Untitled (Autodesk Fusion 360 design; units mm, degrees)
Autodesk Fusion 360 part; units mm, degrees
note: some values were not read from the file. Set by a fixed rule: which face or edge a step refers to.
other "Base Mesh Feature1"
sketch "Sketch1" plane through (0, 0, 0) normal (0, 1, 0) x (1, 0, 0)
sketch "Sketch2" plane through (0, 0, 0) normal (0, 0, 1) x (1, 0, 0)
  line L0 (1, 1) -> (38, 1)
  line L1 (38, 1) -> (38, -19)
  line L2 (38, -19) -> (1, -19)
  line L3 (1, -19) -> (1, 1)
  line L4 (38, -9.5531) -> (28, -9.5531)
  line L5 (28, -9.5531) -> (28, -8.4531)
  line L6 (28, -8.4531) -> (38, -8.4531)
  line L7 (38, -8.4531) -> (38, -9.5531)
  line L8 (1, -9.5536) -> (11, -9.5536)
  line L9 (11, -9.5536) -> (11, -8.4536)
  line L10 (11, -8.4536) -> (1, -8.4536)
  line L11 (1, -8.4536) -> (1, -9.5536)
  dimension "d1" = 10
  dimension "d2" = 1.1
  dimension "d3" = 10
  dimension "d4" = 1.1
  constraint horizontal L0
  constraint vertical L1
  constraint horizontal L2
  constraint vertical L3
  constraint horizontal L4
  constraint vertical L5
  constraint horizontal L6
  constraint vertical L7
  constraint coincident L1 L4.start
  constraint horizontal L8
  constraint vertical L9
  constraint horizontal L10
  constraint vertical L11
  constraint coincident L3 L8.start
  measures "d1" distance of L4.start L4.end
  measures "d2" distance of L4.start L6.end
  measures "d3" distance of L8.start L8.end
  measures "d4" distance of L8.start L10.end
sketch "Sketch3" plane through (0, 0, 0) normal (1, 0, 0) x (0, 0, -1)
extrude "Extrude1" add sketch "Sketch2" along normal blind 29 makes body 1
extrude "Extrude2" cut sketch "Sketch2" along normal blind 22 contours L3 L8 L9 L10 L11 | L1 L4 L5 L6 L7 bodies 1
sketch "Sketch4" plane through (0, -19, 0) normal (0, -1, 0) x (1, 0, 0)
  line L0 (1, 0) -> (38, 0)
  line L1 (38, 0) -> (38, 29)
  line L2 (38, 29) -> (1, 29)
  line L3 (1, 29) -> (1, 0)
  line L4 (38, 0) -> (65.5, 0)
  line L5 (65.5, 0) -> (65.5, 29)
  line L6 (65.5, 29) -> (38, 29)
  line L7 (38, 29) -> (38, 0)
  dimension "d11" = 27.5
  dimension "d12" = 29
  constraint horizontal L4
  constraint vertical L5
  constraint horizontal L6
  constraint vertical L7
  constraint coincident L0.end L1.start
  measures "d11" distance of L0.end L4.end
  measures "d12" distance of L0.end L1.end
extrude "Extrude3" add sketch "Sketch4" against normal blind 9 separate body contours L1 L4 L5 L6 L7 makes body 2
sketch "Sketch5" plane through (0, -19, 0) normal (0, -1, 0) x (1, 0, 0)
  line L0 (38, 29) -> (38, 0)
  line L1 (38, 0) -> (65.5, 0)
  line L2 (65.5, 0) -> (65.5, 29)
  line L3 (65.5, 29) -> (38, 29)
  line L4 (65.5, 29) -> (78.5, 29)
  line L5 (78.5, 29) -> (78.5, 0)
  line L6 (78.5, 0) -> (65.5, 0)
  line L7 (65.5, 0) -> (65.5, 29)
  constraint horizontal L4
  constraint vertical L5
  constraint horizontal L6
  constraint vertical L7
  constraint coincident L2.end L3.start
extrude "Extrude4" add sketch "Sketch5" along normal blind 27.5 and the other way blind 9 contours L2 L4 L5 L6 L7 bodies 2
copy_body "CopyPasteBodies1" bodies 1 makes body 3
move_body "Move1" bodies 3 to x (0, -1, 0) y (1, 0, 0) z (0, 0, 1) at (84.4226, -51.1247, 0)
move_body "Move2" bodies 3 to x (1, 0, 0) y (0, 1, 0) z (0, 0, 1) at (0.0774, 5.6247, 0)
sketch "Sketch6" plane through (0, -19, 0) normal (0, -1, 0) x (1, 0, 0)
  line L0 (1, 0) -> (38, 0)
  line L1 (38, 0) -> (38, 29)
  line L2 (38, 29) -> (1, 29)
  line L3 (1, 29) -> (1, 0)
  line L4 (1, 29) -> (38, 29)
  line L5 (38, 29) -> (38, 0)
  line L6 (38, 0) -> (1, 0)
  line L7 (1, 0) -> (1, 29)
  constraint horizontal L4
  constraint vertical L5
  constraint horizontal L6
  constraint vertical L7
  constraint coincident L0.end L1.start
  constraint coincident L2.end L3.start
extrude "Extrude5" add sketch "Sketch6" along normal blind 64.5 bodies 1
extrude "Extrude6" add 1 faces at (65.5, -71.1667, 9.6667) along direction (-1, 0, 0) blind 64.5 on bodies 3 bodies 3 1
chamfer "Chamfer1" distance 15 angle 45 1 edges at (1, -83.5, 14.5) tangent chain off on bodies 3
chamfer "Chamfer2" distance 15 angle 45 1 edges at (38, -46.5, 14.5) tangent chain off on bodies 3
extrude "Extrude7" cut 1 faces at (76.0464, -53.1667, 7.3333) along direction (1, 0, 0) blind 0.001 on bodies 3 bodies 3
extrude "Extrude8" add 1 faces at (76.0474, -53.1667, 7.3333) along direction (-1, 0, 0) blind 0.7 on bodies 3 bodies 3
extrude "Extrude9" add 1 faces at (76.0469, -76.8333, 7.3333) along direction (-1, 0, 0) blind 0.7 on bodies 3 bodies 3
extrude "Extrude10" add 1 faces at (31.3333, -8.4531, 7.3333) along direction (0, -1, 0) blind 0.7 on bodies 3 bodies 3
sketch "Sketch7" plane through (0, -8.4536, 0) normal (0, -1, 0) x (1, 0, 0)
  line L0 (1, 0) -> (11, 0)
  line L1 (11, 0) -> (11, 22)
  line L2 (11, 22) -> (1, 22)
  line L3 (1, 22) -> (1, 0)
extrude "Extrude11" add sketch "Sketch7" along normal blind 0.7 bodies 3
extrude "Extrude12" cut 1 faces at (34.6667, -9.5531, 7.3333) along direction (0, -1, 0) blind 0.25 on bodies 3 bodies 3
extrude "Extrude13" cut 1 faces at (4.3333, -9.5536, 7.3333) along direction (0, -1, 0) blind 0.25 on bodies 3 bodies 3
extrude "Extrude14" cut 1 faces at (74.9464, -49.8333, 7.3333) along direction (-1, 0, 0) blind 0.25 on bodies 3 bodies 3
extrude "Extrude15" cut 1 faces at (74.9469, -80.1667, 7.3333) along direction (-1, 0, 0) blind 0.25 on bodies 3 bodies 3
chamfer "Chamfer3" distance 3 angle 45 8 edges at (33, -9.1531, 0) (33, -9.8031, 0) (6, -9.1536, 0) (6, -9.8036, 0) (74.6964, -51.5, 0) (75.3474, -51.5, 0) (74.6969, -78.5, 0) (75.3469, -78.5, 0) tangent chain off on bodies 3
fillet "Fillet1" radius 2 4 edges at (38, -31.5, 14.5) (53, -46.5, 14.5) (16, -83.5, 14.5) (1, -68.5, 14.5) on bodies 3
hidden bodies 2
